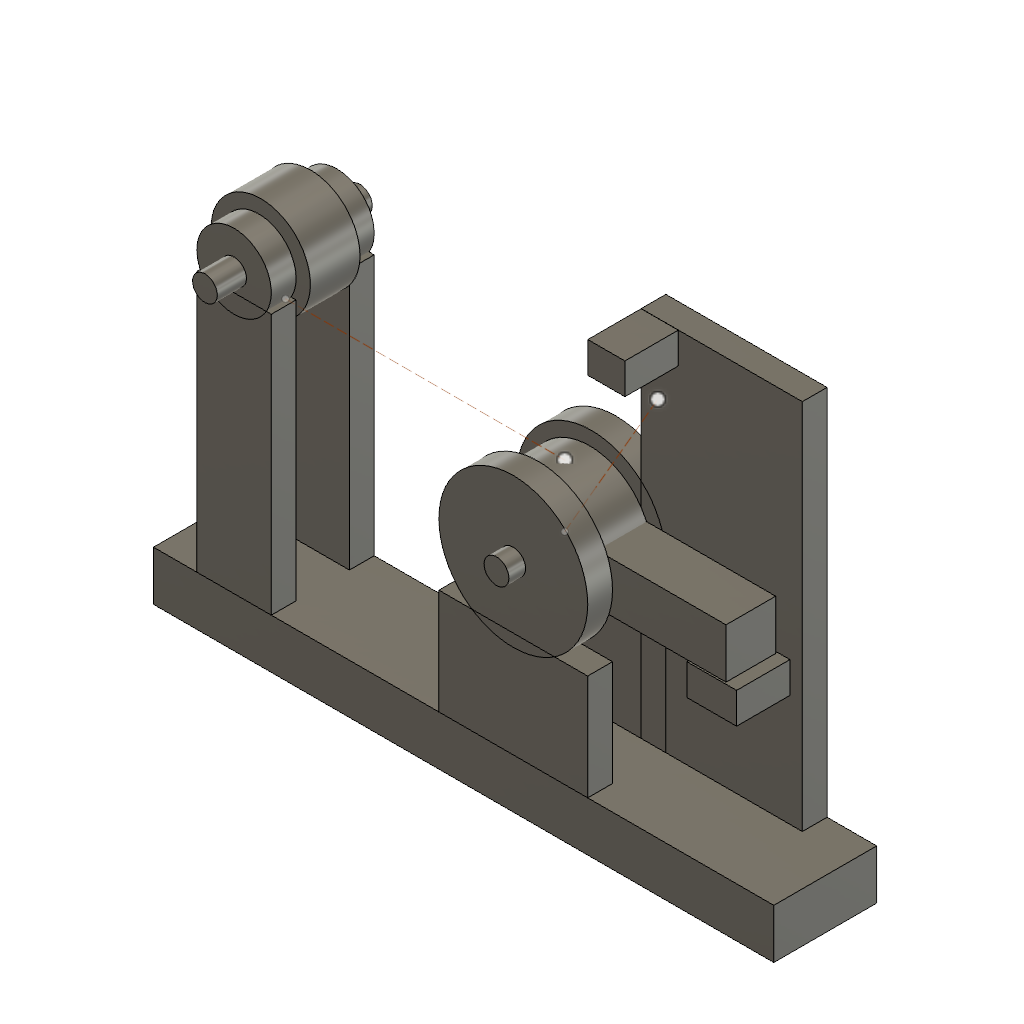
tendon-gripper-envelopes (Autodesk Fusion 360 design; units mm, degrees)
part number: 2026-11-06-12-59-03-254
part number: 2026-11-06-12-59-03-461
part number: 2026-11-06-12-59-03-473
part number: 2026-11-06-12-59-03-488
part number: 2026-11-06-12-59-03-501
part number: 2026-11-06-12-59-03-518
part number: 2026-11-06-12-59-03-533
part number: 2026-11-06-12-59-03-553
part number: 2026-11-06-12-59-03-569
part number: 2026-11-06-12-59-03-588
part number: 2026-11-06-12-59-03-611
part number: 2026-11-06-12-59-03-629
part number: 2026-11-06-12-59-03-656
part number: 2026-11-06-12-59-03-678
part number: 2026-11-06-12-59-03-709
part number: 2026-11-06-12-59-03-734
part number: 2026-11-06-12-59-03-760
part number: 2026-11-06-12-59-03-785
Autodesk Fusion 360 part; units mm, degrees
sketch "Metal hinge pin envelope section" plane through (0, 0, 0) normal (0, 0, 1) x (1, 0, 0) in component "Metal hinge pin envelope"
  circle A0 centre (0, 0) radius 2
  dimension "d14" = 4
  constraint coincident A0.centre origin
  measures "d14" diameter of A0
extrude "Metal hinge pin envelope length" add sketch "Metal hinge pin envelope section" along normal blind 22 makes body 1 in component "Metal hinge pin envelope"
sketch "Finger sector PITCH surface no groove section" plane through (0, 0, 0) normal (0, 0, 1) x (1, 0, 0) in component "Finger sector PITCH surface no groove"
  circle A0 centre (0, 0) radius 10
  circle A1 centre (0, 0) radius 2
  dimension "d17" = 20
  dimension "d18" = 4
  constraint coincident A0.centre A1.centre
  measures "d17" diameter of A0
  measures "d18" diameter of A1
extrude "Finger sector PITCH surface no groove length" add sketch "Finger sector PITCH surface no groove section" along normal blind 8 separate body makes body 2 in component "Finger sector PITCH surface no groove"
sketch "Finger arm envelope footprint" plane through (0, 0, 0) normal (0, 0, 1) x (1, 0, 0) in component "Finger arm envelope"
  line L0 (0, 0) -> (30, 0)
  line L1 (30, 0) -> (30, 8)
  line L2 (30, 8) -> (0, 8)
  line L3 (0, 8) -> (0, 0)
extrude "Finger arm envelope thickness" add sketch "Finger arm envelope footprint" along normal blind 8 separate body makes body 3 in component "Finger arm envelope"
sketch "Clevis front hinge envelope section" plane through (0, 0, 0) normal (0, 0, 1) x (1, 0, 0) in component "Clevis front hinge envelope"
  circle A0 centre (0, 0) radius 12
  circle A1 centre (0, 0) radius 2
  dimension "d23" = 24
  dimension "d24" = 4
  constraint coincident A0.centre A1.centre
  measures "d23" diameter of A0
  measures "d24" diameter of A1
extrude "Clevis front hinge envelope length" add sketch "Clevis front hinge envelope section" along normal blind 4 separate body makes body 4 in component "Clevis front hinge envelope"
sketch "Clevis front leg envelope footprint" plane through (0, 0, 0) normal (0, 0, 1) x (1, 0, 0) in component "Clevis front leg envelope"
  line L0 (0, 0) -> (24, 0)
  line L1 (24, 0) -> (24, 17)
  line L2 (24, 17) -> (0, 17)
  line L3 (0, 17) -> (0, 0)
extrude "Clevis front leg envelope thickness" add sketch "Clevis front leg envelope footprint" along normal blind 4 separate body makes body 5 in component "Clevis front leg envelope"
sketch "Clevis rear hinge envelope section" plane through (0, 0, 0) normal (0, 0, 1) x (1, 0, 0) in component "Clevis rear hinge envelope"
  circle A0 centre (0, 0) radius 12
  circle A1 centre (0, 0) radius 2
  dimension "d29" = 24
  dimension "d30" = 4
  constraint coincident A0.centre A1.centre
  measures "d29" diameter of A0
  measures "d30" diameter of A1
extrude "Clevis rear hinge envelope length" add sketch "Clevis rear hinge envelope section" along normal blind 4 separate body makes body 6 in component "Clevis rear hinge envelope"
sketch "Clevis rear leg envelope footprint" plane through (0, 0, 0) normal (0, 0, 1) x (1, 0, 0) in component "Clevis rear leg envelope"
  line L0 (0, 0) -> (24, 0)
  line L1 (24, 0) -> (24, 17)
  line L2 (24, 17) -> (0, 17)
  line L3 (0, 17) -> (0, 0)
extrude "Clevis rear leg envelope thickness" add sketch "Clevis rear leg envelope footprint" along normal blind 4 separate body makes body 7 in component "Clevis rear leg envelope"
sketch "Base envelope footprint" plane through (0, 0, 0) normal (0, 0, 1) x (1, 0, 0) in component "Base envelope"
  line L0 (0, 0) -> (100, 0)
  line L1 (100, 0) -> (100, 8)
  line L2 (100, 8) -> (0, 8)
  line L3 (0, 8) -> (0, 0)
extrude "Base envelope thickness" add sketch "Base envelope footprint" along normal blind 16.6 separate body makes body 8 in component "Base envelope"
sketch "Spool PITCH surface no groove section" plane through (0, 0, 0) normal (0, 0, 1) x (1, 0, 0) in component "Spool PITCH surface no groove"
  circle A0 centre (0, 0) radius 8
  circle A1 centre (0, 0) radius 2
  dimension "d37" = 16
  dimension "d38" = 4
  constraint coincident A0.centre A1.centre
  measures "d37" diameter of A0
  measures "d38" diameter of A1
extrude "Spool PITCH surface no groove length" add sketch "Spool PITCH surface no groove section" along normal blind 8 separate body makes body 9 in component "Spool PITCH surface no groove"
sketch "Spool shaft envelope section" plane through (0, 0, 0) normal (0, 0, 1) x (1, 0, 0) in component "Spool shaft envelope"
  circle A0 centre (0, 0) radius 2
  dimension "d41" = 4
  constraint coincident A0.centre origin
  measures "d41" diameter of A0
extrude "Spool shaft envelope length" add sketch "Spool shaft envelope section" along normal blind 25 separate body makes body 10 in component "Spool shaft envelope"
sketch "Spool bearing support front envelope section" plane through (0, 0, 0) normal (0, 0, 1) x (1, 0, 0) in component "Spool bearing support front envelope"
  circle A0 centre (0, 0) radius 6
  circle A1 centre (0, 0) radius 2
  dimension "d44" = 12
  dimension "d45" = 4
  constraint coincident A0.centre A1.centre
  measures "d44" diameter of A0
  measures "d45" diameter of A1
extrude "Spool bearing support front envelope length" add sketch "Spool bearing support front envelope section" along normal blind 4 separate body makes body 11 in component "Spool bearing support front envelope"
sketch "Spool support front leg envelope footprint" plane through (0, 0, 0) normal (0, 0, 1) x (1, 0, 0) in component "Spool support front leg envelope"
  line L0 (0, 0) -> (12, 0)
  line L1 (12, 0) -> (12, 42)
  line L2 (12, 42) -> (0, 42)
  line L3 (0, 42) -> (0, 0)
extrude "Spool support front leg envelope thickness" add sketch "Spool support front leg envelope footprint" along normal blind 4 separate body makes body 12 in component "Spool support front leg envelope"
sketch "Spool bearing support rear envelope section" plane through (0, 0, 0) normal (0, 0, 1) x (1, 0, 0) in component "Spool bearing support rear envelope"
  circle A0 centre (0, 0) radius 6
  circle A1 centre (0, 0) radius 2
  dimension "d50" = 12
  dimension "d51" = 4
  constraint coincident A0.centre A1.centre
  measures "d50" diameter of A0
  measures "d51" diameter of A1
extrude "Spool bearing support rear envelope length" add sketch "Spool bearing support rear envelope section" along normal blind 4 separate body makes body 13 in component "Spool bearing support rear envelope"
sketch "Spool support rear leg envelope footprint" plane through (0, 0, 0) normal (0, 0, 1) x (1, 0, 0) in component "Spool support rear leg envelope"
  line L0 (0, 0) -> (12, 0)
  line L1 (12, 0) -> (12, 42)
  line L2 (12, 42) -> (0, 42)
  line L3 (0, 42) -> (0, 0)
extrude "Spool support rear leg envelope thickness" add sketch "Spool support rear leg envelope footprint" along normal blind 4 separate body makes body 14 in component "Spool support rear leg envelope"
sketch "Stop support far-side plate envelope footprint" plane through (0, 0, 0) normal (0, 0, 1) x (1, 0, 0) in component "Stop support far-side plate envelope"
  line L0 (0, 0) -> (26, 0)
  line L1 (26, 0) -> (26, 60)
  line L2 (26, 60) -> (0, 60)
  line L3 (0, 60) -> (0, 0)
extrude "Stop support far-side plate envelope thickness" add sketch "Stop support far-side plate envelope footprint" along normal blind 4 separate body makes body 15 in component "Stop support far-side plate envelope"
sketch "Open-stop nominal contact at 0deg footprint" plane through (0, 0, 0) normal (0, 0, 1) x (1, 0, 0) in component "Open-stop nominal contact at 0deg"
  line L0 (0, 0) -> (8, 0)
  line L1 (8, 0) -> (8, 5)
  line L2 (8, 5) -> (0, 5)
  line L3 (0, 5) -> (0, 0)
extrude "Open-stop nominal contact at 0deg thickness" add sketch "Open-stop nominal contact at 0deg footprint" along normal blind 8.6 separate body makes body 16 in component "Open-stop nominal contact at 0deg"
sketch "Closed-stop nominal contact at 60deg footprint" plane through (0, 0, 0) normal (0, 0, 1) x (1, 0, 0) in component "Closed-stop nominal contact at 60deg"
  line L0 (0, 0) -> (6, 0)
  line L1 (6, 0) -> (6, 5)
  line L2 (6, 5) -> (0, 5)
  line L3 (0, 5) -> (0, 0)
extrude "Closed-stop nominal contact at 60deg thickness" add sketch "Closed-stop nominal contact at 60deg footprint" along normal blind 8.6 separate body makes body 17 in component "Closed-stop nominal contact at 60deg"
ref_plane "WorkPlane1" through (0, 0, 4) normal (0, 0, 1) x (1, 0, 0)
sketch "Tendon tangent and 60deg travel reference" plane through (0, 0, 4) normal (0, 0, 1) x (1, 0, 0)
  line L0 (-45, 10) -> (0, 10) construction
  line L1 (0, 0) -> (15, 25.9808) construction
component "Metal hinge pin envelope" placed x (1, 0, 0) y (0, 1, 0) z (0, 0, 1) at (0, 0, -7)
component "Finger sector PITCH surface no groove" placed x (1, 0, 0) y (0, 1, 0) z (0, 0, 1) at (0, 0, 0)
component "Finger arm envelope" placed x (1, 0, 0) y (0, 1, 0) z (0, 0, 1) at (0, -4, 0)
component "Clevis front hinge envelope" placed x (1, 0, 0) y (0, 1, 0) z (0, 0, 1) at (0, 0, -4.3)
component "Clevis front leg envelope" placed x (1, 0, 0) y (0, 1, 0) z (0, 0, 1) at (-12, -27, -4.3)
component "Clevis rear hinge envelope" placed x (1, 0, 0) y (0, 1, 0) z (0, 0, 1) at (0, 0, 8.3)
component "Clevis rear leg envelope" placed x (1, 0, 0) y (0, 1, 0) z (0, 0, 1) at (-12, -27, 8.3)
component "Base envelope" placed x (1, 0, 0) y (0, 1, 0) z (0, 0, 1) at (-58, -35, -4.3)
component "Spool PITCH surface no groove" placed x (1, 0, 0) y (0, 1, 0) z (0, 0, 1) at (-45, 18, 0)
component "Spool shaft envelope" placed x (1, 0, 0) y (0, 1, 0) z (0, 0, 1) at (-45, 18, -8)
component "Spool bearing support front envelope" placed x (1, 0, 0) y (0, 1, 0) z (0, 0, 1) at (-45, 18, -4.3)
component "Spool support front leg envelope" placed x (1, 0, 0) y (0, 1, 0) z (0, 0, 1) at (-51, -27, -4.3)
component "Spool bearing support rear envelope" placed x (1, 0, 0) y (0, 1, 0) z (0, 0, 1) at (-45, 18, 8.3)
component "Spool support rear leg envelope" placed x (1, 0, 0) y (0, 1, 0) z (0, 0, 1) at (-51, -27, 8.3)
component "Stop support far-side plate envelope" placed x (1, 0, 0) y (0, 1, 0) z (0, 0, 1) at (8, -27, -4.3)
component "Open-stop nominal contact at 0deg" placed x (1, 0, 0) y (0, 1, 0) z (0, 0, 1) at (24, -9, -0.3)
component "Closed-stop nominal contact at 60deg" placed x (1, 0, 0) y (0, 1, 0) z (0, 0, 1) at (8, 27.9808, -0.3)
equation "tip_moment_arm = 30 mm" comment "Study reference input; envelope positions require manual regeneration"
equation "tendon_radius = 10 mm" comment "Study reference input; envelope positions require manual regeneration"
equation "spool_radius = 8 mm" comment "Study reference input; envelope positions require manual regeneration"
equation "finger_rotation = 60 deg" comment "Study reference input; envelope positions require manual regeneration"
equation "tendon_travel = 10.471975511965978 mm" comment "Study reference input; envelope positions require manual regeneration"
equation "spool_rotation = 75 deg" comment "Study reference input; envelope positions require manual regeneration"
equation "hinge_diameter = 4 mm" comment "Study reference input; envelope positions require manual regeneration"
equation "finger_thickness = 8 mm" comment "Study reference input; envelope positions require manual regeneration"
equation "clevis_gap = 8.6 mm" comment "Study reference input; envelope positions require manual regeneration"
equation "cheek_thickness = 4 mm" comment "Study reference input; envelope positions require manual regeneration"
equation "tendon_plane_z = 4 mm" comment "Study reference input; envelope positions require manual regeneration"
equation "spool_center_x = -45 mm" comment "Study reference input; envelope positions require manual regeneration"
equation "spool_center_y = 18 mm" comment "Study reference input; envelope positions require manual regeneration"
named bodies: "Metal hinge pin envelope", "Finger sector PITCH surface no groove", "Finger arm envelope", "Clevis front hinge envelope", "Clevis front leg envelope", "Clevis rear hinge envelope", "Clevis rear leg envelope", "Base envelope", "Spool PITCH surface no groove", "Spool shaft envelope", "Spool bearing support front envelope", "Spool support front leg envelope", "Spool bearing support rear envelope", "Spool support rear leg envelope", "Stop support far-side plate envelope", "Open-stop nominal contact at 0deg", "Closed-stop nominal contact at 60deg"
